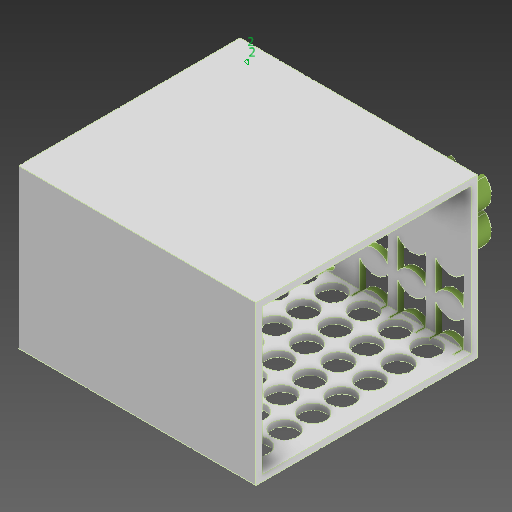
# Autodesk Inventor part: Wednsday19Aug
Saved by Autodesk Inventor 2026.1 (Build 301233020, 233B)
## iProperties
Created: 2026-08-19
Part Number: Wednsday19Aug
Material: Generic
Document SubType Name: Modeling
Designer: YmCris
Density: 1 g/cm^3
Appearance: Olive Green
Author: YmCris
Autodesk Inventor part; units mm, degrees
ref_plane "YZ Plane" through (0, 0, 0) normal (1, 0, 0) x (0, 1, 0)
ref_plane "XZ Plane" through (0, 0, 0) normal (0, 1, 0) x (-1, 0, 0)
ref_plane "XY Plane" through (0, 0, 0) normal (0, 0, 1) x (1, 0, 0)
sketch "Sketch1" plane through (0, 0, 0) normal (0, 0, 1) x (1, 0, 0)
  line L0 (37.5, -25) -> (-37.5, -25)
  line L1 (-37.5, -25) -> (-37.5, 25)
  line L2 (-37.5, 25) -> (37.5, 25)
  line L3 (37.5, 25) -> (37.5, -25)
  line L4 (37.5, -25) -> (-37.5, 25) construction
  line L5 (-37.5, -25) -> (37.5, 25) construction
  point P0 (0, 0)
  dimension "d0" = 75
  dimension "d1" = 50
  constraints: 12 end point, 2 midpoint, 2 parallel, 1 horizontal, 1 perpendicular
  measures "d0" distance of L1.end L2.end
  measures "d1" distance of L0.end L1.end
extrude "Extrusion1" add sketch "Sketch1" along normal blind 70
shell "Shell1" thickness 2 removed faces 1 at (37.5, -8.3333, 23.3333)
sketch "Sketch2" plane through (-37.5, -25, 0) normal (0, -1, 0) x (1, 0, 0)
  line L0 (0, 0) -> (75, 0) construction
  line L1 (0, 0) -> (0, 28.25) construction
  line L2 (0, 0) -> (0, 70) construction
  line L3 (0, 0) -> (25.2723, 0) construction
  circle A0 centre (6.258, 7.213) radius 4
  circle A1 centre (16.258, 7.213) radius 4
  circle A2 centre (26.258, 7.213) radius 4
  circle A3 centre (36.258, 7.213) radius 4
  circle A4 centre (46.258, 7.213) radius 4
  circle A5 centre (56.258, 7.213) radius 4
  circle A6 centre (66.258, 7.213) radius 4
  circle A7 centre (6.258, 16.213) radius 4
  circle A8 centre (16.258, 16.213) radius 4
  circle A9 centre (26.258, 16.213) radius 4
  circle A10 centre (36.258, 16.213) radius 4
  circle A11 centre (46.258, 16.213) radius 4
  circle A12 centre (56.258, 16.213) radius 4
  circle A13 centre (66.258, 16.213) radius 4
  circle A14 centre (6.258, 25.213) radius 4
  circle A15 centre (16.258, 25.213) radius 4
  circle A16 centre (26.258, 25.213) radius 4
  circle A17 centre (36.258, 25.213) radius 4
  circle A18 centre (46.258, 25.213) radius 4
  circle A19 centre (56.258, 25.213) radius 4
  circle A20 centre (66.258, 25.213) radius 4
  circle A21 centre (6.258, 34.213) radius 4
  circle A22 centre (16.258, 34.213) radius 4
  circle A23 centre (26.258, 34.213) radius 4
  circle A24 centre (36.258, 34.213) radius 4
  circle A25 centre (46.258, 34.213) radius 4
  circle A26 centre (56.258, 34.213) radius 4
  circle A27 centre (66.258, 34.213) radius 4
  circle A28 centre (6.258, 43.213) radius 4
  circle A29 centre (16.258, 43.213) radius 4
  circle A30 centre (26.258, 43.213) radius 4
  circle A31 centre (36.258, 43.213) radius 4
  circle A32 centre (46.258, 43.213) radius 4
  circle A33 centre (56.258, 43.213) radius 4
  circle A34 centre (66.258, 43.213) radius 4
  circle A35 centre (6.258, 52.213) radius 4
  circle A36 centre (16.258, 52.213) radius 4
  circle A37 centre (26.258, 52.213) radius 4
  circle A38 centre (36.258, 52.213) radius 4
  circle A39 centre (46.258, 52.213) radius 4
  circle A40 centre (56.258, 52.213) radius 4
  circle A41 centre (66.258, 52.213) radius 4
  circle A42 centre (6.258, 61.213) radius 4
  circle A43 centre (16.258, 61.213) radius 4
  circle A44 centre (26.258, 61.213) radius 4
  circle A45 centre (36.258, 61.213) radius 4
  circle A46 centre (46.258, 61.213) radius 4
  circle A47 centre (56.258, 61.213) radius 4
  circle A48 centre (66.258, 61.213) radius 4
  point P0 (37.5, 0)
  dimension "d5" = 8
  dimension "d8" = 10
  dimension "d11" = 9
  constraints: 49 centre point, 4 end point, 2 horizontal, 1 point on line, 1 vertical, 96 other
  measures "d5" diameter of A0
  measures "d8" distance of A0.centre A1.centre
  measures "d11" distance of A0.centre A7.centre
extrude "Extrusion2" cut sketch "Sketch2" against normal blind 5
sketch "Sketch3" plane through (0, 0, 0) normal (0, 0, -1) x (-1, 0, 0)
  arc A0 (-35.1302, -14.4398) -> (-26.3456, -14.2946) centre (-30.7874, -11.3756) ccw
  arc A1 (-26.3456, -23.7833) -> (-35.1302, -23.6381) centre (-30.7874, -26.7023) ccw
  line L0 (-35.1302, -23.6381) -> (-35.1302, -14.4398)
  line L1 (35.5, -23) -> (-37.5, -23) construction
  line L2 (-37.5, -25) -> (-34.695, -25)
  line L3 (37.5, -25) -> (-37.5, -25) projected
  line L4 (-37.5, -25) -> (-37.5, 25) projected
  line L5 (-37.5, -25) -> (-37.5, -22.0197)
  line L6 (-26.3456, -23.7833) -> (-26.3456, -14.2946)
  arc A2 (-23.1302, -14.4398) -> (-14.3456, -14.2946) centre (-18.7874, -11.3756) ccw
  arc A3 (-14.3456, -23.7833) -> (-23.1302, -23.6381) centre (-18.7874, -26.7023) ccw
  line L7 (-23.1302, -23.6381) -> (-23.1302, -14.4398)
  line L8 (-14.3456, -23.7833) -> (-14.3456, -14.2946)
  arc A4 (-11.1302, -14.4398) -> (-2.3456, -14.2946) centre (-6.7874, -11.3756) ccw
  arc A5 (-2.3456, -23.7833) -> (-11.1302, -23.6381) centre (-6.7874, -26.7023) ccw
  line L9 (-11.1302, -23.6381) -> (-11.1302, -14.4398)
  line L10 (-2.3456, -23.7833) -> (-2.3456, -14.2946)
  arc A6 (-35.1302, -2.4398) -> (-26.3456, -2.2946) centre (-30.7874, 0.6244) ccw
  arc A7 (-26.3456, -11.7833) -> (-35.1302, -11.6381) centre (-30.7874, -14.7023) ccw
  line L11 (-35.1302, -11.6381) -> (-35.1302, -2.4398) construction
  line L12 (-26.3456, -11.7833) -> (-26.3456, -2.2946)
  arc A8 (-23.1302, -2.4398) -> (-14.3456, -2.2946) centre (-18.7874, 0.6244) ccw
  arc A9 (-14.3456, -11.7833) -> (-23.1302, -11.6381) centre (-18.7874, -14.7023) ccw
  line L13 (-23.1302, -11.6381) -> (-23.1302, -2.4398)
  line L14 (-14.3456, -11.7833) -> (-14.3456, -2.2946)
  arc A10 (-11.1302, -2.4398) -> (-2.3456, -2.2946) centre (-6.7874, 0.6244) ccw
  arc A11 (-2.3456, -11.7833) -> (-11.1302, -11.6381) centre (-6.7874, -14.7023) ccw
  line L15 (-11.1302, -11.6381) -> (-11.1302, -2.4398)
  line L16 (-2.3456, -11.7833) -> (-2.3456, -2.2946)
  line L17 (-35.1302, -11.6381) -> (-35.1302, -2.4398)
  point P0 (0, 0)
  dimension "d18" = 12
  dimension "d21" = 12
  constraints: 30 end point, 30 point on circle, 12 centre point, 2 point on line, 2 vertical, 1 collinear, 1 horizontal, 1 perpendicular, 55 other
  measures "d18" distance of L0.end L7.end
  measures "d21" distance of L0.end L11.end
extrude "Extrusion3" cut sketch "Sketch3" against normal blind 5
sketch "Sketch4" plane through (0, 0, 0) normal (0, 0, -1) x (-1, 0, 0)
  ellipse E0 centre (30.0044, -20.2361) end of major axis (25.5278, -20.2361) minor radius 3.0489
  line L0 (37.2449, -25) -> (31.242, -25) construction
  line L1 (35.242, -25) -> (27.242, -25) construction
  line L2 (37.5, 25) -> (37.5, -25) construction
  line L3 (37.5, -25) -> (37.5, -18.5758) construction
  ellipse E1 centre (30.0044, -12.2361) end of major axis (25.5278, -12.2361) minor radius 3.0489
  ellipse E2 centre (30.0044, -4.2361) end of major axis (25.5278, -4.2361) minor radius 3.0489
  ellipse E3 centre (20.0044, -20.2361) end of major axis (15.5278, -20.2361) minor radius 3.0489
  ellipse E4 centre (20.0044, -12.2361) end of major axis (15.5278, -12.2361) minor radius 3.0489
  ellipse E5 centre (20.0044, -4.2361) end of major axis (15.5278, -4.2361) minor radius 3.0489
  ellipse E6 centre (10.0044, -20.2361) end of major axis (5.5278, -20.2361) minor radius 3.0489
  ellipse E7 centre (10.0044, -12.2361) end of major axis (5.5278, -12.2361) minor radius 3.0489
  ellipse E8 centre (10.0044, -4.2361) end of major axis (5.5278, -4.2361) minor radius 3.0489
  point P0 (0, 0)
  dimension "d28" = 8
  dimension "d31" = 10
  constraints: 7 horizontal, 4 end point, 3 vertical, 1 midpoint, 1 point on line, 26 other
  measures "d28" distance of point (30.004, -20.236) point (30.004, -12.236)
  measures "d31" distance of point (30.004, -20.236) point (20.004, -20.236)
extrude "Extrusion4" cut sketch "Sketch4" against normal blind 5
sketch "Sketch5" plane through (0, 0, 0) normal (0, 0, -1) x (-1, 0, 0)
  arc A0 (-34.4081, 10.3154) -> (-34.4509, 2.9172) centre (-30.8355, 6.5956) ccw construction
  arc A1 (-35.0528, 10.9867) -> (-35.1032, 2.2535) centre (-30.8355, 6.5956) ccw
  arc A2 (-33.7634, 9.6442) -> (-33.7985, 3.581) centre (-30.8355, 6.5956) ccw
  arc A3 (-33.7634, 9.6442) -> (-35.0528, 10.9867) centre (-34.4081, 10.3154) ccw
  arc A4 (-35.1032, 2.2535) -> (-33.7985, 3.581) centre (-34.4509, 2.9172) ccw
  circle A5 centre (-31.7427, 4.3169) radius 1.4618
  circle A6 centre (-31.7427, 8.3668) radius 1.5844
  line L0 (-37.5, -25) -> (-37.5, 25) construction
  line L1 (-37.5, 0.3433) -> (-37.5, 5.7786) construction
  line L2 (-37.5, 0) -> (-32.1247, 0) construction
  arc A7 (-24.4081, 10.3154) -> (-24.4509, 2.9172) centre (-20.8355, 6.5956) ccw construction
  arc A8 (-25.0528, 10.9867) -> (-25.1032, 2.2535) centre (-20.8355, 6.5956) ccw
  arc A9 (-23.7634, 9.6442) -> (-23.7985, 3.581) centre (-20.8355, 6.5956) ccw
  arc A10 (-23.7634, 9.6442) -> (-25.0528, 10.9867) centre (-24.4081, 10.3154) ccw
  arc A11 (-25.1032, 2.2535) -> (-23.7985, 3.581) centre (-24.4509, 2.9172) ccw
  circle A12 centre (-21.7427, 4.3169) radius 1.4618
  circle A13 centre (-21.7427, 8.3668) radius 1.5844
  line L3 (-27.5, 0) -> (-22.1247, 0) construction
  arc A14 (-34.4081, 20.3154) -> (-34.4509, 12.9172) centre (-30.8355, 16.5956) ccw construction
  arc A15 (-35.0528, 20.9867) -> (-35.1032, 12.2535) centre (-30.8355, 16.5956) ccw
  arc A16 (-33.7634, 19.6442) -> (-33.7985, 13.581) centre (-30.8355, 16.5956) ccw
  arc A17 (-33.7634, 19.6442) -> (-35.0528, 20.9867) centre (-34.4081, 20.3154) ccw
  arc A18 (-35.1032, 12.2535) -> (-33.7985, 13.581) centre (-34.4509, 12.9172) ccw
  circle A19 centre (-31.7427, 14.3169) radius 1.4618
  circle A20 centre (-31.7427, 18.3668) radius 1.5844
  line L4 (-37.5, 10) -> (-32.1247, 10) construction
  arc A21 (-24.4081, 20.3154) -> (-24.4509, 12.9172) centre (-20.8355, 16.5956) ccw construction
  arc A22 (-25.0528, 20.9867) -> (-25.1032, 12.2535) centre (-20.8355, 16.5956) ccw
  arc A23 (-23.7634, 19.6442) -> (-23.7985, 13.581) centre (-20.8355, 16.5956) ccw
  arc A24 (-23.7634, 19.6442) -> (-25.0528, 20.9867) centre (-24.4081, 20.3154) ccw
  arc A25 (-25.1032, 12.2535) -> (-23.7985, 13.581) centre (-24.4509, 12.9172) ccw
  circle A26 centre (-21.7427, 14.3169) radius 1.4618
  circle A27 centre (-21.7427, 18.3668) radius 1.5844
  line L5 (-27.5, 10) -> (-22.1247, 10) construction
  point P0 (0, 0)
  dimension "d38" = 10
  dimension "d41" = 10
  constraints: 40 point on circle, 28 centre point, 10 end point, 4 tangent, 2 horizontal, 2 point on line, 1 collinear, 1 midpoint, 1 vertical, 56 other
  measures "d38" distance of A0.start A7.start
  measures "d41" distance of A0.start A14.start
extrude "Extrusion5" add sketch "Sketch5" along normal blind 5
sketch "Sketch6" plane through (0, 0, 0) normal (0, 0, -1) x (-1, 0, 0)
  circle A0 centre (34.9712, 23.2992) radius 1
  circle A1 centre (34.9712, 20.7805) radius 1
  ellipse E0 centre (32.966, 22.1988) end of major axis (32.966, 21.3674) minor radius 0.9017
  arc A2 (36.5484, 22.5045) -> (36.524, 24.1062) centre (35.9487, 23.2964) ccw construction
  arc A3 (36.6935, 22.313) -> (36.6631, 24.302) centre (35.9487, 23.2964) ccw
  arc A4 (36.4034, 22.696) -> (36.3849, 23.9104) centre (35.9487, 23.2964) ccw
  arc A5 (36.4034, 22.696) -> (36.6935, 22.313) centre (36.5484, 22.5045) ccw
  arc A6 (36.6631, 24.302) -> (36.3849, 23.9104) centre (36.524, 24.1062) ccw
  arc A7 (36.524, 19.8997) -> (36.5484, 21.5014) centre (35.9487, 20.7096) ccw construction
  arc A8 (36.6631, 19.7039) -> (36.6935, 21.6929) centre (35.9487, 20.7096) ccw
  arc A9 (36.3849, 20.0956) -> (36.4034, 21.31) centre (35.9487, 20.7096) ccw
  arc A10 (36.6935, 21.6929) -> (36.4034, 21.31) centre (36.5484, 21.5014) ccw
  arc A11 (36.3849, 20.0956) -> (36.6631, 19.7039) centre (36.524, 19.8997) ccw
  point P0 (0, 0)
  dimension "d46" = 2
  dimension "d47" = 2
  constraints: 20 point on circle, 13 centre point, 4 tangent, 1 other
  measures "d46" diameter of A0
  measures "d47" diameter of A1
body "Solid1"
